Autodesk Fusion 360 part; units mm, degrees
(part 8 of 8)
sketch "693ZZ inner race | profile (14)" plane through (0, 0, -6) normal (0, 0, 1) x (1, 0, 0) in component "11:1 twin-disc elbow | original geometry"
  circle A0 centre (-25.9808, -15) radius 2.5
  circle A1 centre (-25.9808, -15) radius 1.5
extrude "693ZZ inner race (14)" add sketch "693ZZ inner race | profile (14)" along normal blind 4 separate body makes body 385 in component "11:1 twin-disc elbow | original geometry"
ref_plane "WorkPlane66" through (0, 0, -5.85) normal (0, 0, 1) x (1, 0, 0) in component "11:1 twin-disc elbow | original geometry"
sketch "693ZZ shield | profile (14)" plane through (0, 0, -5.85) normal (0, 0, 1) x (1, 0, 0) in component "11:1 twin-disc elbow | original geometry"
  circle A0 centre (-25.9808, -15) radius 3
  circle A1 centre (-25.9808, -15) radius 2.5
extrude "693ZZ shield (14)" add sketch "693ZZ shield | profile (14)" along normal blind 3.7 separate body makes body 386 in component "11:1 twin-disc elbow | original geometry"
ref_plane "WorkPlane67" through (0, 0, 2) normal (0, 0, 1) x (1, 0, 0) in component "11:1 twin-disc elbow | original geometry"
sketch "693ZZ outer race | profile (15)" plane through (0, 0, 2) normal (0, 0, 1) x (1, 0, 0) in component "11:1 twin-disc elbow | original geometry"
  circle A0 centre (-25.9808, -15) radius 4
  circle A1 centre (-25.9808, -15) radius 3
extrude "693ZZ outer race (15)" add sketch "693ZZ outer race | profile (15)" along normal blind 4 separate body makes body 387 in component "11:1 twin-disc elbow | original geometry"
ref_plane "WorkPlane68" through (0, 0, 2) normal (0, 0, 1) x (1, 0, 0) in component "11:1 twin-disc elbow | original geometry"
sketch "693ZZ inner race | profile (15)" plane through (0, 0, 2) normal (0, 0, 1) x (1, 0, 0) in component "11:1 twin-disc elbow | original geometry"
  circle A0 centre (-25.9808, -15) radius 2.5
  circle A1 centre (-25.9808, -15) radius 1.5
extrude "693ZZ inner race (15)" add sketch "693ZZ inner race | profile (15)" along normal blind 4 separate body makes body 388 in component "11:1 twin-disc elbow | original geometry"
ref_plane "WorkPlane69" through (0, 0, 2.15) normal (0, 0, 1) x (1, 0, 0) in component "11:1 twin-disc elbow | original geometry"
sketch "693ZZ shield | profile (15)" plane through (0, 0, 2.15) normal (0, 0, 1) x (1, 0, 0) in component "11:1 twin-disc elbow | original geometry"
  circle A0 centre (-25.9808, -15) radius 3
  circle A1 centre (-25.9808, -15) radius 2.5
extrude "693ZZ shield (15)" add sketch "693ZZ shield | profile (15)" along normal blind 3.7 separate body makes body 389 in component "11:1 twin-disc elbow | original geometry"
ref_plane "WorkPlane70" through (0, 0, -17) normal (0, 0, 1) x (1, 0, 0) in component "11:1 twin-disc elbow | original geometry"
sketch "Fixed metal roller pin 9 | profile (2)" plane through (0, 0, -17) normal (0, 0, 1) x (1, 0, 0) in component "11:1 twin-disc elbow | original geometry"
  circle A0 centre (-15, -25.9808) radius 1.5
extrude "Fixed metal roller pin 9'" add sketch "Fixed metal roller pin 9 | profile (2)" along normal blind 34 separate body makes body 390 in component "11:1 twin-disc elbow | original geometry"
ref_plane "WorkPlane71" through (0, 0, -6) normal (0, 0, 1) x (1, 0, 0) in component "11:1 twin-disc elbow | original geometry"
sketch "693ZZ outer race | profile (16)" plane through (0, 0, -6) normal (0, 0, 1) x (1, 0, 0) in component "11:1 twin-disc elbow | original geometry"
  circle A0 centre (-15, -25.9808) radius 4
  circle A1 centre (-15, -25.9808) radius 3
extrude "693ZZ outer race (16)" add sketch "693ZZ outer race | profile (16)" along normal blind 4 separate body makes body 391 in component "11:1 twin-disc elbow | original geometry"
ref_plane "WorkPlane72" through (0, 0, -6) normal (0, 0, 1) x (1, 0, 0) in component "11:1 twin-disc elbow | original geometry"
sketch "693ZZ inner race | profile (16)" plane through (0, 0, -6) normal (0, 0, 1) x (1, 0, 0) in component "11:1 twin-disc elbow | original geometry"
  circle A0 centre (-15, -25.9808) radius 2.5
  circle A1 centre (-15, -25.9808) radius 1.5
extrude "693ZZ inner race (16)" add sketch "693ZZ inner race | profile (16)" along normal blind 4 separate body makes body 392 in component "11:1 twin-disc elbow | original geometry"
ref_plane "WorkPlane73" through (0, 0, -5.85) normal (0, 0, 1) x (1, 0, 0) in component "11:1 twin-disc elbow | original geometry"
sketch "693ZZ shield | profile (16)" plane through (0, 0, -5.85) normal (0, 0, 1) x (1, 0, 0) in component "11:1 twin-disc elbow | original geometry"
  circle A0 centre (-15, -25.9808) radius 3
  circle A1 centre (-15, -25.9808) radius 2.5
extrude "693ZZ shield (16)" add sketch "693ZZ shield | profile (16)" along normal blind 3.7 separate body makes body 393 in component "11:1 twin-disc elbow | original geometry"
ref_plane "WorkPlane74" through (0, 0, 2) normal (0, 0, 1) x (1, 0, 0) in component "11:1 twin-disc elbow | original geometry"
sketch "693ZZ outer race | profile (17)" plane through (0, 0, 2) normal (0, 0, 1) x (1, 0, 0) in component "11:1 twin-disc elbow | original geometry"
  circle A0 centre (-15, -25.9808) radius 4
  circle A1 centre (-15, -25.9808) radius 3
extrude "693ZZ outer race (17)" add sketch "693ZZ outer race | profile (17)" along normal blind 4 separate body makes body 394 in component "11:1 twin-disc elbow | original geometry"
ref_plane "WorkPlane75" through (0, 0, 2) normal (0, 0, 1) x (1, 0, 0) in component "11:1 twin-disc elbow | original geometry"
sketch "693ZZ inner race | profile (17)" plane through (0, 0, 2) normal (0, 0, 1) x (1, 0, 0) in component "11:1 twin-disc elbow | original geometry"
  circle A0 centre (-15, -25.9808) radius 2.5
  circle A1 centre (-15, -25.9808) radius 1.5
extrude "693ZZ inner race (17)" add sketch "693ZZ inner race | profile (17)" along normal blind 4 separate body makes body 395 in component "11:1 twin-disc elbow | original geometry"
ref_plane "WorkPlane76" through (0, 0, 2.15) normal (0, 0, 1) x (1, 0, 0) in component "11:1 twin-disc elbow | original geometry"
sketch "693ZZ shield | profile (17)" plane through (0, 0, 2.15) normal (0, 0, 1) x (1, 0, 0) in component "11:1 twin-disc elbow | original geometry"
  circle A0 centre (-15, -25.9808) radius 3
  circle A1 centre (-15, -25.9808) radius 2.5
extrude "693ZZ shield (17)" add sketch "693ZZ shield | profile (17)" along normal blind 3.7 separate body makes body 396 in component "11:1 twin-disc elbow | original geometry"
ref_plane "WorkPlane77" through (0, 0, -17) normal (0, 0, 1) x (1, 0, 0) in component "11:1 twin-disc elbow | original geometry"
sketch "Fixed metal roller pin 10 | profile (2)" plane through (0, 0, -17) normal (0, 0, 1) x (1, 0, 0) in component "11:1 twin-disc elbow | original geometry"
  circle A0 centre (0, -30) radius 1.5
extrude "Fixed metal roller pin 10'" add sketch "Fixed metal roller pin 10 | profile (2)" along normal blind 34 separate body makes body 397 in component "11:1 twin-disc elbow | original geometry"
ref_plane "WorkPlane78" through (0, 0, -6) normal (0, 0, 1) x (1, 0, 0) in component "11:1 twin-disc elbow | original geometry"
sketch "693ZZ outer race | profile (18)" plane through (0, 0, -6) normal (0, 0, 1) x (1, 0, 0) in component "11:1 twin-disc elbow | original geometry"
  circle A0 centre (0, -30) radius 4
  circle A1 centre (0, -30) radius 3
extrude "693ZZ outer race (18)" add sketch "693ZZ outer race | profile (18)" along normal blind 4 separate body makes body 398 in component "11:1 twin-disc elbow | original geometry"
ref_plane "WorkPlane79" through (0, 0, -6) normal (0, 0, 1) x (1, 0, 0) in component "11:1 twin-disc elbow | original geometry"
sketch "693ZZ inner race | profile (18)" plane through (0, 0, -6) normal (0, 0, 1) x (1, 0, 0) in component "11:1 twin-disc elbow | original geometry"
  circle A0 centre (0, -30) radius 2.5
  circle A1 centre (0, -30) radius 1.5
extrude "693ZZ inner race (18)" add sketch "693ZZ inner race | profile (18)" along normal blind 4 separate body makes body 399 in component "11:1 twin-disc elbow | original geometry"
ref_plane "WorkPlane80" through (0, 0, -5.85) normal (0, 0, 1) x (1, 0, 0) in component "11:1 twin-disc elbow | original geometry"
sketch "693ZZ shield | profile (18)" plane through (0, 0, -5.85) normal (0, 0, 1) x (1, 0, 0) in component "11:1 twin-disc elbow | original geometry"
  circle A0 centre (0, -30) radius 3
  circle A1 centre (0, -30) radius 2.5
extrude "693ZZ shield (18)" add sketch "693ZZ shield | profile (18)" along normal blind 3.7 separate body makes body 400 in component "11:1 twin-disc elbow | original geometry"
ref_plane "WorkPlane81" through (0, 0, 2) normal (0, 0, 1) x (1, 0, 0) in component "11:1 twin-disc elbow | original geometry"
sketch "693ZZ outer race | profile (19)" plane through (0, 0, 2) normal (0, 0, 1) x (1, 0, 0) in component "11:1 twin-disc elbow | original geometry"
  circle A0 centre (0, -30) radius 4
  circle A1 centre (0, -30) radius 3
extrude "693ZZ outer race (19)" add sketch "693ZZ outer race | profile (19)" along normal blind 4 separate body makes body 401 in component "11:1 twin-disc elbow | original geometry"
ref_plane "WorkPlane82" through (0, 0, 2) normal (0, 0, 1) x (1, 0, 0) in component "11:1 twin-disc elbow | original geometry"
sketch "693ZZ inner race | profile (19)" plane through (0, 0, 2) normal (0, 0, 1) x (1, 0, 0) in component "11:1 twin-disc elbow | original geometry"
  circle A0 centre (0, -30) radius 2.5
  circle A1 centre (0, -30) radius 1.5
extrude "693ZZ inner race (19)" add sketch "693ZZ inner race | profile (19)" along normal blind 4 separate body makes body 402 in component "11:1 twin-disc elbow | original geometry"
ref_plane "WorkPlane83" through (0, 0, 2.15) normal (0, 0, 1) x (1, 0, 0) in component "11:1 twin-disc elbow | original geometry"
sketch "693ZZ shield | profile (19)" plane through (0, 0, 2.15) normal (0, 0, 1) x (1, 0, 0) in component "11:1 twin-disc elbow | original geometry"
  circle A0 centre (0, -30) radius 3
  circle A1 centre (0, -30) radius 2.5
extrude "693ZZ shield (19)" add sketch "693ZZ shield | profile (19)" along normal blind 3.7 separate body makes body 403 in component "11:1 twin-disc elbow | original geometry"
ref_plane "WorkPlane84" through (0, 0, -17) normal (0, 0, 1) x (1, 0, 0) in component "11:1 twin-disc elbow | original geometry"
sketch "Fixed metal roller pin 11 | profile (2)" plane through (0, 0, -17) normal (0, 0, 1) x (1, 0, 0) in component "11:1 twin-disc elbow | original geometry"
  circle A0 centre (15, -25.9808) radius 1.5
extrude "Fixed metal roller pin 11'" add sketch "Fixed metal roller pin 11 | profile (2)" along normal blind 34 separate body makes body 404 in component "11:1 twin-disc elbow | original geometry"
ref_plane "WorkPlane85" through (0, 0, -6) normal (0, 0, 1) x (1, 0, 0) in component "11:1 twin-disc elbow | original geometry"
sketch "693ZZ outer race | profile (20)" plane through (0, 0, -6) normal (0, 0, 1) x (1, 0, 0) in component "11:1 twin-disc elbow | original geometry"
  circle A0 centre (15, -25.9808) radius 4
  circle A1 centre (15, -25.9808) radius 3
extrude "693ZZ outer race (20)" add sketch "693ZZ outer race | profile (20)" along normal blind 4 separate body makes body 405 in component "11:1 twin-disc elbow | original geometry"
ref_plane "WorkPlane86" through (0, 0, -6) normal (0, 0, 1) x (1, 0, 0) in component "11:1 twin-disc elbow | original geometry"
sketch "693ZZ inner race | profile (20)" plane through (0, 0, -6) normal (0, 0, 1) x (1, 0, 0) in component "11:1 twin-disc elbow | original geometry"
  circle A0 centre (15, -25.9808) radius 2.5
  circle A1 centre (15, -25.9808) radius 1.5
extrude "693ZZ inner race (20)" add sketch "693ZZ inner race | profile (20)" along normal blind 4 separate body makes body 406 in component "11:1 twin-disc elbow | original geometry"
ref_plane "WorkPlane87" through (0, 0, -5.85) normal (0, 0, 1) x (1, 0, 0) in component "11:1 twin-disc elbow | original geometry"
sketch "693ZZ shield | profile (20)" plane through (0, 0, -5.85) normal (0, 0, 1) x (1, 0, 0) in component "11:1 twin-disc elbow | original geometry"
  circle A0 centre (15, -25.9808) radius 3
  circle A1 centre (15, -25.9808) radius 2.5
extrude "693ZZ shield (20)" add sketch "693ZZ shield | profile (20)" along normal blind 3.7 separate body makes body 407 in component "11:1 twin-disc elbow | original geometry"
ref_plane "WorkPlane88" through (0, 0, 2) normal (0, 0, 1) x (1, 0, 0) in component "11:1 twin-disc elbow | original geometry"
sketch "693ZZ outer race | profile (21)" plane through (0, 0, 2) normal (0, 0, 1) x (1, 0, 0) in component "11:1 twin-disc elbow | original geometry"
  circle A0 centre (15, -25.9808) radius 4
  circle A1 centre (15, -25.9808) radius 3
extrude "693ZZ outer race (21)" add sketch "693ZZ outer race | profile (21)" along normal blind 4 separate body makes body 408 in component "11:1 twin-disc elbow | original geometry"
ref_plane "WorkPlane89" through (0, 0, 2) normal (0, 0, 1) x (1, 0, 0) in component "11:1 twin-disc elbow | original geometry"
sketch "693ZZ inner race | profile (21)" plane through (0, 0, 2) normal (0, 0, 1) x (1, 0, 0) in component "11:1 twin-disc elbow | original geometry"
  circle A0 centre (15, -25.9808) radius 2.5
  circle A1 centre (15, -25.9808) radius 1.5
extrude "693ZZ inner race (21)" add sketch "693ZZ inner race | profile (21)" along normal blind 4 separate body makes body 409 in component "11:1 twin-disc elbow | original geometry"
ref_plane "WorkPlane90" through (0, 0, 2.15) normal (0, 0, 1) x (1, 0, 0) in component "11:1 twin-disc elbow | original geometry"
sketch "693ZZ shield | profile (21)" plane through (0, 0, 2.15) normal (0, 0, 1) x (1, 0, 0) in component "11:1 twin-disc elbow | original geometry"
  circle A0 centre (15, -25.9808) radius 3
  circle A1 centre (15, -25.9808) radius 2.5
extrude "693ZZ shield (21)" add sketch "693ZZ shield | profile (21)" along normal blind 3.7 separate body makes body 410 in component "11:1 twin-disc elbow | original geometry"
ref_plane "WorkPlane91" through (0, 0, -17) normal (0, 0, 1) x (1, 0, 0) in component "11:1 twin-disc elbow | original geometry"
sketch "Fixed metal roller pin 12 | profile (2)" plane through (0, 0, -17) normal (0, 0, 1) x (1, 0, 0) in component "11:1 twin-disc elbow | original geometry"
  circle A0 centre (25.9808, -15) radius 1.5
extrude "Fixed metal roller pin 12'" add sketch "Fixed metal roller pin 12 | profile (2)" along normal blind 34 separate body makes body 411 in component "11:1 twin-disc elbow | original geometry"
ref_plane "WorkPlane92" through (0, 0, -6) normal (0, 0, 1) x (1, 0, 0) in component "11:1 twin-disc elbow | original geometry"
sketch "693ZZ outer race | profile (22)" plane through (0, 0, -6) normal (0, 0, 1) x (1, 0, 0) in component "11:1 twin-disc elbow | original geometry"
  circle A0 centre (25.9808, -15) radius 4
  circle A1 centre (25.9808, -15) radius 3
extrude "693ZZ outer race (22)" add sketch "693ZZ outer race | profile (22)" along normal blind 4 separate body makes body 412 in component "11:1 twin-disc elbow | original geometry"
ref_plane "WorkPlane93" through (0, 0, -6) normal (0, 0, 1) x (1, 0, 0) in component "11:1 twin-disc elbow | original geometry"
sketch "693ZZ inner race | profile (22)" plane through (0, 0, -6) normal (0, 0, 1) x (1, 0, 0) in component "11:1 twin-disc elbow | original geometry"
  circle A0 centre (25.9808, -15) radius 2.5
  circle A1 centre (25.9808, -15) radius 1.5
extrude "693ZZ inner race (22)" add sketch "693ZZ inner race | profile (22)" along normal blind 4 separate body makes body 413 in component "11:1 twin-disc elbow | original geometry"
ref_plane "WorkPlane94" through (0, 0, -5.85) normal (0, 0, 1) x (1, 0, 0) in component "11:1 twin-disc elbow | original geometry"
sketch "693ZZ shield | profile (22)" plane through (0, 0, -5.85) normal (0, 0, 1) x (1, 0, 0) in component "11:1 twin-disc elbow | original geometry"
  circle A0 centre (25.9808, -15) radius 3
  circle A1 centre (25.9808, -15) radius 2.5
extrude "693ZZ shield (22)" add sketch "693ZZ shield | profile (22)" along normal blind 3.7 separate body makes body 414 in component "11:1 twin-disc elbow | original geometry"
ref_plane "WorkPlane95" through (0, 0, 2) normal (0, 0, 1) x (1, 0, 0) in component "11:1 twin-disc elbow | original geometry"
sketch "693ZZ outer race | profile (23)" plane through (0, 0, 2) normal (0, 0, 1) x (1, 0, 0) in component "11:1 twin-disc elbow | original geometry"
  circle A0 centre (25.9808, -15) radius 4
  circle A1 centre (25.9808, -15) radius 3
extrude "693ZZ outer race (23)" add sketch "693ZZ outer race | profile (23)" along normal blind 4 separate body makes body 415 in component "11:1 twin-disc elbow | original geometry"
ref_plane "WorkPlane96" through (0, 0, 2) normal (0, 0, 1) x (1, 0, 0) in component "11:1 twin-disc elbow | original geometry"
sketch "693ZZ inner race | profile (23)" plane through (0, 0, 2) normal (0, 0, 1) x (1, 0, 0) in component "11:1 twin-disc elbow | original geometry"
  circle A0 centre (25.9808, -15) radius 2.5
  circle A1 centre (25.9808, -15) radius 1.5
extrude "693ZZ inner race (23)" add sketch "693ZZ inner race | profile (23)" along normal blind 4 separate body makes body 416 in component "11:1 twin-disc elbow | original geometry"
ref_plane "WorkPlane97" through (0, 0, 2.15) normal (0, 0, 1) x (1, 0, 0) in component "11:1 twin-disc elbow | original geometry"
sketch "693ZZ shield | profile (23)" plane through (0, 0, 2.15) normal (0, 0, 1) x (1, 0, 0) in component "11:1 twin-disc elbow | original geometry"
  circle A0 centre (25.9808, -15) radius 3
  circle A1 centre (25.9808, -15) radius 2.5
extrude "693ZZ shield (23)" add sketch "693ZZ shield | profile (23)" along normal blind 3.7 separate body makes body 417 in component "11:1 twin-disc elbow | original geometry"
ref_plane "WorkPlane98" through (0, 0, -11) normal (0, 0, 1) x (1, 0, 0) in component "11:1 twin-disc elbow | original geometry"
sketch "Output carrier bridge | profile (2)" plane through (0, 0, -11) normal (0, 0, 1) x (1, 0, 0) in component "11:1 twin-disc elbow | original geometry"
  circle A0 centre (0, 0) radius 23
  circle A1 centre (0, 0) radius 8
extrude "Output carrier bridge'" add sketch "Output carrier bridge | profile (2)" along normal blind 3 separate body makes body 418 in component "11:1 twin-disc elbow | original geometry"
ref_plane "WorkPlane99" through (0, 0, 8) normal (0, 0, 1) x (1, 0, 0) in component "11:1 twin-disc elbow | original geometry"
sketch "Output carrier bridge | profile (1) (2)" plane through (0, 0, 8) normal (0, 0, 1) x (1, 0, 0) in component "11:1 twin-disc elbow | original geometry"
  circle A0 centre (0, 0) radius 23
  circle A1 centre (0, 0) radius 8
extrude "Output carrier bridge (1)'" add sketch "Output carrier bridge | profile (1) (2)" along normal blind 3 separate body makes body 419 in component "11:1 twin-disc elbow | original geometry"
ref_plane "WorkPlane100" through (0, 0, -11) normal (0, 0, 1) x (1, 0, 0) in component "11:1 twin-disc elbow | original geometry"
sketch "Steel output pin 1 | profile (2)" plane through (0, 0, -11) normal (0, 0, 1) x (1, 0, 0) in component "11:1 twin-disc elbow | original geometry"
  circle A0 centre (18, 0) radius 1.5
extrude "Steel output pin 1'" add sketch "Steel output pin 1 | profile (2)" along normal blind 22 separate body makes body 420 in component "11:1 twin-disc elbow | original geometry"
ref_plane "WorkPlane101" through (0, 0, -11) normal (0, 0, 1) x (1, 0, 0) in component "11:1 twin-disc elbow | original geometry"
sketch "Steel output pin 2 | profile (2)" plane through (0, 0, -11) normal (0, 0, 1) x (1, 0, 0) in component "11:1 twin-disc elbow | original geometry"
  circle A0 centre (9, 15.5885) radius 1.5
extrude "Steel output pin 2'" add sketch "Steel output pin 2 | profile (2)" along normal blind 22 separate body makes body 421 in component "11:1 twin-disc elbow | original geometry"
ref_plane "WorkPlane102" through (0, 0, -11) normal (0, 0, 1) x (1, 0, 0) in component "11:1 twin-disc elbow | original geometry"
sketch "Steel output pin 3 | profile (2)" plane through (0, 0, -11) normal (0, 0, 1) x (1, 0, 0) in component "11:1 twin-disc elbow | original geometry"
  circle A0 centre (-9, 15.5885) radius 1.5
extrude "Steel output pin 3'" add sketch "Steel output pin 3 | profile (2)" along normal blind 22 separate body makes body 422 in component "11:1 twin-disc elbow | original geometry"
ref_plane "WorkPlane103" through (0, 0, -11) normal (0, 0, 1) x (1, 0, 0) in component "11:1 twin-disc elbow | original geometry"
sketch "Steel output pin 4 | profile (2)" plane through (0, 0, -11) normal (0, 0, 1) x (1, 0, 0) in component "11:1 twin-disc elbow | original geometry"
  circle A0 centre (-18, 0) radius 1.5
extrude "Steel output pin 4'" add sketch "Steel output pin 4 | profile (2)" along normal blind 22 separate body makes body 423 in component "11:1 twin-disc elbow | original geometry"
ref_plane "WorkPlane104" through (0, 0, -11) normal (0, 0, 1) x (1, 0, 0) in component "11:1 twin-disc elbow | original geometry"
sketch "Steel output pin 5 | profile (2)" plane through (0, 0, -11) normal (0, 0, 1) x (1, 0, 0) in component "11:1 twin-disc elbow | original geometry"
  circle A0 centre (-9, -15.5885) radius 1.5
extrude "Steel output pin 5'" add sketch "Steel output pin 5 | profile (2)" along normal blind 22 separate body makes body 424 in component "11:1 twin-disc elbow | original geometry"
ref_plane "WorkPlane105" through (0, 0, -11) normal (0, 0, 1) x (1, 0, 0) in component "11:1 twin-disc elbow | original geometry"
sketch "Steel output pin 6 | profile (2)" plane through (0, 0, -11) normal (0, 0, 1) x (1, 0, 0) in component "11:1 twin-disc elbow | original geometry"
  circle A0 centre (9, -15.5885) radius 1.5
extrude "Steel output pin 6'" add sketch "Steel output pin 6 | profile (2)" along normal blind 22 separate body makes body 425 in component "11:1 twin-disc elbow | original geometry"
ref_plane "WorkPlane106" through (0, 0, -24) normal (0, 0, 1) x (1, 0, 0) in component "11:1 twin-disc elbow | original geometry"
sketch "Outboard output hub | profile (2)" plane through (0, 0, -24) normal (0, 0, 1) x (1, 0, 0) in component "11:1 twin-disc elbow | original geometry"
  circle A0 centre (0, 0) radius 15
  circle A1 centre (0, 0) radius 9
extrude "Outboard output hub'" add sketch "Outboard output hub | profile (2)" along normal blind 13 separate body makes body 426 in component "11:1 twin-disc elbow | original geometry"
ref_plane "WorkPlane107" through (0, 0, 11) normal (0, 0, 1) x (1, 0, 0) in component "11:1 twin-disc elbow | original geometry"
sketch "Outboard output hub | profile (1) (2)" plane through (0, 0, 11) normal (0, 0, 1) x (1, 0, 0) in component "11:1 twin-disc elbow | original geometry"
  circle A0 centre (0, 0) radius 15
  circle A1 centre (0, 0) radius 9
extrude "Outboard output hub (1)'" add sketch "Outboard output hub | profile (1) (2)" along normal blind 13 separate body makes body 427 in component "11:1 twin-disc elbow | original geometry"
ref_plane "WorkPlane108" through (0, 0, -24) normal (0, 0, 1) x (1, 0, 0) in component "11:1 twin-disc elbow | original geometry"
sketch "6806 output support outer race | profile (2)" plane through (0, 0, -24) normal (0, 0, 1) x (1, 0, 0) in component "11:1 twin-disc elbow | original geometry"
  circle A0 centre (0, 0) radius 21
  circle A1 centre (0, 0) radius 20
extrude "6806 output support outer race'" add sketch "6806 output support outer race | profile (2)" along normal blind 7 separate body makes body 428 in component "11:1 twin-disc elbow | original geometry"
ref_plane "WorkPlane109" through (0, 0, -24) normal (0, 0, 1) x (1, 0, 0) in component "11:1 twin-disc elbow | original geometry"
sketch "6806 output support inner race | profile (2)" plane through (0, 0, -24) normal (0, 0, 1) x (1, 0, 0) in component "11:1 twin-disc elbow | original geometry"
  circle A0 centre (0, 0) radius 16
  circle A1 centre (0, 0) radius 15
extrude "6806 output support inner race'" add sketch "6806 output support inner race | profile (2)" along normal blind 7 separate body makes body 429 in component "11:1 twin-disc elbow | original geometry"
ref_plane "WorkPlane110" through (0, 0, -23.85) normal (0, 0, 1) x (1, 0, 0) in component "11:1 twin-disc elbow | original geometry"
sketch "6806 output support shield | profile (2)" plane through (0, 0, -23.85) normal (0, 0, 1) x (1, 0, 0) in component "11:1 twin-disc elbow | original geometry"
  circle A0 centre (0, 0) radius 20
  circle A1 centre (0, 0) radius 16
extrude "6806 output support shield'" add sketch "6806 output support shield | profile (2)" along normal blind 6.7 separate body makes body 430 in component "11:1 twin-disc elbow | original geometry"
ref_plane "WorkPlane111" through (0, 0, -24) normal (0, 0, 1) x (1, 0, 0) in component "11:1 twin-disc elbow | original geometry"
sketch "Output bearing collar | profile (2)" plane through (0, 0, -24) normal (0, 0, 1) x (1, 0, 0) in component "11:1 twin-disc elbow | original geometry"
  circle A0 centre (0, 0) radius 26
  circle A1 centre (0, 0) radius 21.1
extrude "Output bearing collar'" add sketch "Output bearing collar | profile (2)" along normal blind 7 separate body makes body 431 in component "11:1 twin-disc elbow | original geometry"
ref_plane "WorkPlane112" through (0, 0, 17) normal (0, 0, 1) x (1, 0, 0) in component "11:1 twin-disc elbow | original geometry"
sketch "6806 output support outer race | profile (1) (2)" plane through (0, 0, 17) normal (0, 0, 1) x (1, 0, 0) in component "11:1 twin-disc elbow | original geometry"
  circle A0 centre (0, 0) radius 21
  circle A1 centre (0, 0) radius 20
extrude "6806 output support outer race (1)'" add sketch "6806 output support outer race | profile (1) (2)" along normal blind 7 separate body makes body 432 in component "11:1 twin-disc elbow | original geometry"
ref_plane "WorkPlane113" through (0, 0, 17) normal (0, 0, 1) x (1, 0, 0) in component "11:1 twin-disc elbow | original geometry"
sketch "6806 output support inner race | profile (1) (2)" plane through (0, 0, 17) normal (0, 0, 1) x (1, 0, 0) in component "11:1 twin-disc elbow | original geometry"
  circle A0 centre (0, 0) radius 16
  circle A1 centre (0, 0) radius 15
extrude "6806 output support inner race (1)'" add sketch "6806 output support inner race | profile (1) (2)" along normal blind 7 separate body makes body 433 in component "11:1 twin-disc elbow | original geometry"
ref_plane "WorkPlane114" through (0, 0, 17.15) normal (0, 0, 1) x (1, 0, 0) in component "11:1 twin-disc elbow | original geometry"
sketch "6806 output support shield | profile (1) (2)" plane through (0, 0, 17.15) normal (0, 0, 1) x (1, 0, 0) in component "11:1 twin-disc elbow | original geometry"
  circle A0 centre (0, 0) radius 20
  circle A1 centre (0, 0) radius 16
extrude "6806 output support shield (1)'" add sketch "6806 output support shield | profile (1) (2)" along normal blind 6.7 separate body makes body 434 in component "11:1 twin-disc elbow | original geometry"
ref_plane "WorkPlane115" through (0, 0, 17) normal (0, 0, 1) x (1, 0, 0) in component "11:1 twin-disc elbow | original geometry"
sketch "Output bearing collar | profile (1) (2)" plane through (0, 0, 17) normal (0, 0, 1) x (1, 0, 0) in component "11:1 twin-disc elbow | original geometry"
  circle A0 centre (0, 0) radius 26
  circle A1 centre (0, 0) radius 21.1
extrude "Output bearing collar (1)'" add sketch "Output bearing collar | profile (1) (2)" along normal blind 7 separate body makes body 435 in component "11:1 twin-disc elbow | original geometry"
ref_plane "WorkPlane116" through (0, 0, -27) normal (0, 0, 1) x (1, 0, 0) in component "11:1 twin-disc elbow | original geometry"
sketch "Steel input shaft | profile (2)" plane through (0, 0, -27) normal (0, 0, 1) x (1, 0, 0) in component "11:1 twin-disc elbow | original geometry"
  circle A0 centre (0, 0) radius 3
extrude "Steel input shaft'" add sketch "Steel input shaft | profile (2)" along normal blind 58 separate body makes body 436 in component "11:1 twin-disc elbow | original geometry"
sketch "Sketch1" plane through (0, 0, 0) normal (0, 0, 1) x (1, 0, 0)
sketch "Sketch2" plane through (0, 0, 0) normal (0, 0, 1) x (1, 0, 0)
sketch "Sketch3" plane through (0, 0, 0) normal (0, 0, 1) x (1, 0, 0)
  point P0 (68.3779, 0)
sketch "Sketch4" plane through (0, 0, 0) normal (0, 0, 1) x (1, 0, 0)
  point P0 (215.7917, 0)
component "01 | Compact faceted base" placed x (1, 0, 0) y (0, 1, 0) z (0, 0, 1) at (0, 0, 0)
component "02 | Flat-sided NEMA23 pedestal" placed x (0, 0, 1) y (-1, 0, 0) z (0, -1, 0) at (0, 0, 190)
component "03 | Straight upper beam" placed x (0.390731, 0, 0.920505) y (-0.920505, 0, 0.390731) z (0, -1, 0) at (0, 0, 190)
component "04 | Straight forearm beam" placed x (0.951057, 0, -0.309017) y (0.309017, 0, 0.951057) z (0, -1, 0) at (68.3779, 0, 351.0883)
component "05 | MG996R gripper cassette" placed x (0, 0, -1) y (1, 0, 0) z (0, -1, 0) at (215.7917, 0, 303.1907)
component "J1 | NEMA17 drawing reference" placed x (1, 0, 0) y (0, 1, 0) z (0, 0, 1) at (-52, 0, 46) in component "01 | Compact faceted base"
component "J2 | NEMA23 drawing reference" placed x (1, 0, 0) y (0, 1, 0) z (0, 0, 1) at (-62, 20, 30) in component "02 | Flat-sided NEMA23 pedestal"
component "11:1 twin-disc shoulder | original geometry" placed x (1, 0, 0) y (0, 1, 0) z (0, 0, 1) at (0, 0, 0) in component "02 | Flat-sided NEMA23 pedestal"
component "J3 | NEMA17 drawing reference" placed x (1, 0, 0) y (0, 1, 0) z (0, 0, 1) at (82, 0, 13) in component "03 | Straight upper beam"
component "11:1 twin-disc elbow | original geometry" placed x (1, 0, 0) y (0, 1, 0) z (0, 0, 1) at (175, 0, 0) in component "03 | Straight upper beam"
component "J4 | NEMA17 drawing reference" placed x (1, 0, 0) y (0, 1, 0) z (0, 0, 1) at (69, 0, 13) in component "04 | Straight forearm beam"
component "MG996R Robot 180 | drawing reconstruction, fit pending" placed x (1, 0, 0) y (0, 1, 0) z (0, 0, 1) at (38, 0, -21.5) in component "05 | MG996R gripper cassette"
named bodies: "White bench mounting plate", "Faceted base enclosure", "Flat white base deck", "Motor mount | metal, stock and holes to finalize", "20T pulley envelope | tooth profile pending", "20T flange", "60T pulley envelope | tooth profile pending", "60T flange", "J1 3:1 span | belt length pending", "J1 3:1 span | belt length pending (1)", "J1 3:1 drive wrap", "J1 3:1 driven wrap", "6004 turntable outer race", "6004 turntable inner race", "6004 turntable shield", "Yaw output shaft", "TPU mounting foot", "TPU mounting foot (1)", "TPU mounting foot (2)", "TPU mounting foot (3)", "Base service screw", "Base service screw (1)", "Base service screw (2)", "Base service screw (3)", "Straight-sided torso frame", "Flat rear torso panel", "Flat front torso panel", "20T pulley envelope | tooth profile pending (1)", "20T flange (1)", "J2 1:1 enclosed span | belt length pending", "J2 1:1 enclosed span | belt length pending (1)", "J2 1:1 enclosed drive wrap", "J2 1:1 enclosed driven wrap", "Shoulder front recessed graphite seam", "Shoulder front narrow white annulus", "Shoulder front flat Green Marble face", "Shoulder front flush M3 head", "Shoulder front flush M3 head (1)", "Shoulder front flush M3 head (2)", "Shoulder front flush M3 head (3)", "Shoulder front flush M3 head (4)", "Shoulder front flush M3 head (5)", "Shoulder rear recessed graphite seam", "Shoulder rear narrow white annulus", "Shoulder rear flat Green Marble face", "Shoulder rear flush M3 head", "Shoulder rear flush M3 head (1)", "Shoulder rear flush M3 head (2)", "Shoulder rear flush M3 head (3)", "Shoulder rear flush M3 head (4)", "Shoulder rear flush M3 head (5)", "Narrow white torso service rail", "Torso panel screw", "Torso panel screw (1)", "Torso panel screw (2)", "Torso panel screw (3)", "Straight beam sidewall -1", "Straight beam sidewall 1", "Rear removable beam panel", "Front removable beam panel", "Proximal bearing cheek", "Proximal bearing cheek (1)", "Internal 1:1 span | belt length pending", "Internal 1:1 span | belt length pending (1)", "Internal 1:1 drive wrap", "Internal 1:1 driven wrap", "Distal flat fork cheek", "Distal flat fork cheek (1)", "Elbow recessed graphite seam", "Elbow narrow white annulus", "Elbow flat Green Marble face", "Elbow flush M3 head", "Elbow flush M3 head (1)", "Elbow flush M3 head (2)", "Elbow flush M3 head (3)", "Elbow flush M3 head (4)", "Elbow flush M3 head (5)", "Thin white longitudinal rail", "Beam service fastener", "Beam service fastener (1)", "Beam service fastener (2)", "Beam service fastener (3)", "Output coupling sleeve | fastener detail pending", "Output coupling sleeve | fastener detail pending (1)", "80T pulley envelope | tooth profile pending", "80T flange", "Internal 4:1 span | belt length pending", "Internal 4:1 span | belt length pending (1)", "Internal 4:1 drive wrap", "Internal 4:1 driven wrap", "Wrist recessed graphite seam", "Wrist narrow white annulus", "Wrist flat Green Marble face", "Wrist flush M3 head", "Wrist flush M3 head (1)", "Wrist flush M3 head (2)", "Wrist flush M3 head (3)", "Wrist flush M3 head (4)", "Wrist flush M3 head (5)", "6001 independent wrist support outer race", "6001 independent wrist support inner race", "6001 independent wrist support shield", "Wrist output spindle", "MG996R palm cassette sidewall 0", "MG996R palm cassette sidewall 1", "MG996R palm cassette sidewall 3", "MG996R palm cassette sidewall 4", "MG996R palm cassette sidewall 5", "Palm rear service panel", "Flat Green Marble palm cover", "Servo ear rail | adjustable, purchased fit pending", "Servo rail support post", "Servo rail support post (1)", "Servo ear rail | adjustable, purchased fit pending (1)", "Servo rail support post (2)", "Servo rail support post (3)", "Finger pivot support bridge", "Finger pivot support post", "Finger pivot support post (1)", "Finger pivot support post (2)", "Finger pivot support post (3)", "Finger plain bushing | fit pending", "Finger plain bushing | fit pending (1)", "Straight finger -1", "Replaceable TPU gripping pad -1", "Straight finger 1", "Replaceable TPU gripping pad 1", "Palm service screw", "Palm service screw (1)", "Palm service screw (2)", "Palm service screw (3)", "Finger pivot shaft", "Finger gear envelope | meshing geometry pending", "Finger pivot shaft (1)", "Finger gear envelope | meshing geometry pending (1)", "Servo horn to pulley adapter | spline and fastener pending", "Gripper servo drive | routing study span | belt length pending", "Gripper servo drive | routing study span | belt length pending (1)", "Gripper servo drive | routing study drive wrap", "Gripper servo drive | routing study driven wrap", "Stator casing | nominal drawing", "Rear end bell", "Front mounting flange", "Pilot boss", "D output shaft | protrusion from mounting face", "Cable connector", "MG996R case | 40.7 x 19.7 x 37 nominal", "MG996R top cover", "MG996R boss | offset is provisional", "MG996R spline envelope | purchased fit pending", "MG996R nominal ear | verify hole pattern", "MG996R nominal ear | verify hole pattern (1)", "MG996R case screw", "MG996R case screw (1)", "MG996R case screw (2)", "MG996R case screw (3)", "Fixed ring | 12 roller stations", "Rear roller support", "Front roller support", "Cycloidal disc A | 11 lobes", "Eccentric bearing A outer race", "Eccentric bearing A inner race", "Eccentric bearing A shield", "Steel eccentric cam A", "Cycloidal disc B | 11 lobes", "Eccentric bearing B outer race", "Eccentric bearing B inner race", "Eccentric bearing B shield", "Steel eccentric cam B", "Fixed metal roller pin 1", "623ZZ outer race", "623ZZ inner race", "623ZZ shield", "623ZZ outer race (1)", "623ZZ inner race (1)", "623ZZ shield (1)", "Fixed metal roller pin 2", "623ZZ outer race (2)", "623ZZ inner race (2)", "623ZZ shield (2)", "623ZZ outer race (3)", "623ZZ inner race (3)", "623ZZ shield (3)", "Fixed metal roller pin 3", "623ZZ outer race (4)", "623ZZ inner race (4)", "623ZZ shield (4)", "623ZZ outer race (5)", "623ZZ inner race (5)", "623ZZ shield (5)", "Fixed metal roller pin 4", "623ZZ outer race (6)", "623ZZ inner race (6)", "623ZZ shield (6)", "623ZZ outer race (7)", "623ZZ inner race (7)", "623ZZ shield (7)", "Fixed metal roller pin 5", "623ZZ outer race (8)", "623ZZ inner race (8)", "623ZZ shield (8)", "623ZZ outer race (9)", "623ZZ inner race (9)", "623ZZ shield (9)", "Fixed metal roller pin 6", "623ZZ outer race (10)", "623ZZ inner race (10)", "623ZZ shield (10)", "623ZZ outer race (11)", "623ZZ inner race (11)", "623ZZ shield (11)", "Fixed metal roller pin 7", "623ZZ outer race (12)", "623ZZ inner race (12)", "623ZZ shield (12)", "623ZZ outer race (13)", "623ZZ inner race (13)", "623ZZ shield (13)", "Fixed metal roller pin 8", "623ZZ outer race (14)", "623ZZ inner race (14)", "623ZZ shield (14)", "623ZZ outer race (15)", "623ZZ inner race (15)", "623ZZ shield (15)", "Fixed metal roller pin 9", "623ZZ outer race (16)", "623ZZ inner race (16)", "623ZZ shield (16)", "623ZZ outer race (17)", "623ZZ inner race (17)", "623ZZ shield (17)", "Fixed metal roller pin 10", "623ZZ outer race (18)", "623ZZ inner race (18)", "623ZZ shield (18)", "623ZZ outer race (19)", "623ZZ inner race (19)", "623ZZ shield (19)", "Fixed metal roller pin 11", "623ZZ outer race (20)", "623ZZ inner race (20)", "623ZZ shield (20)", "623ZZ outer race (21)", "623ZZ inner race (21)", "623ZZ shield (21)", "Fixed metal roller pin 12", "623ZZ outer race (22)", "623ZZ inner race (22)", "623ZZ shield (22)", "623ZZ outer race (23)", "623ZZ inner race (23)", "623ZZ shield (23)", "Output carrier bridge", "Output carrier bridge (1)", "Steel output pin 1", "Steel output pin 2", "Steel output pin 3", "Steel output pin 4", "Steel output pin 5", "Steel output pin 6", "Outboard output hub", "Outboard output hub (1)", "6806 output support outer race", "6806 output support inner race", "6806 output support shield", "Output bearing collar", "6806 output support outer race (1)", "6806 output support inner race (1)", "6806 output support shield (1)", "Output bearing collar (1)", "Steel input shaft", "693ZZ outer race", "693ZZ inner race", "693ZZ shield", "693ZZ outer race (1)", "693ZZ inner race (1)", "693ZZ shield (1)", "693ZZ outer race (2)", "693ZZ inner race (2)", "693ZZ shield (2)", "693ZZ outer race (3)", "693ZZ inner race (3)", "693ZZ shield (3)", "693ZZ outer race (4)", "693ZZ inner race (4)", "693ZZ shield (4)", "693ZZ outer race (5)", "693ZZ inner race (5)", "693ZZ shield (5)", "693ZZ outer race (6)", "693ZZ inner race (6)", "693ZZ shield (6)", "693ZZ outer race (7)", "693ZZ inner race (7)", "693ZZ shield (7)", "693ZZ outer race (8)", "693ZZ inner race (8)", "693ZZ shield (8)", "693ZZ outer race (9)", "693ZZ inner race (9)", "693ZZ shield (9)", "693ZZ outer race (10)", "693ZZ inner race (10)", "693ZZ shield (10)", "693ZZ outer race (11)", "693ZZ inner race (11)", "693ZZ shield (11)", "693ZZ outer race (12)", "693ZZ inner race (12)", "693ZZ shield (12)", "693ZZ outer race (13)", "693ZZ inner race (13)", "693ZZ shield (13)", "693ZZ outer race (14)", "693ZZ inner race (14)", "693ZZ shield (14)", "693ZZ outer race (15)", "693ZZ inner race (15)", "693ZZ shield (15)", "693ZZ outer race (16)", "693ZZ inner race (16)", "693ZZ shield (16)", "693ZZ outer race (17)", "693ZZ inner race (17)", "693ZZ shield (17)", "693ZZ outer race (18)", "693ZZ inner race (18)", "693ZZ shield (18)", "693ZZ outer race (19)", "693ZZ inner race (19)", "693ZZ shield (19)", "693ZZ outer race (20)", "693ZZ inner race (20)", "693ZZ shield (20)", "693ZZ outer race (21)", "693ZZ inner race (21)", "693ZZ shield (21)", "693ZZ outer race (22)", "693ZZ inner race (22)", "693ZZ shield (22)", "693ZZ outer race (23)", "693ZZ inner race (23)", "693ZZ shield (23)"
